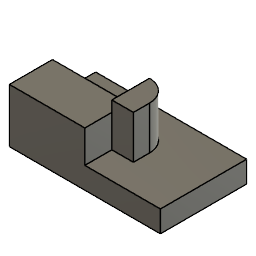
rectangle (Autodesk Fusion 360 design; units mm, degrees)
part number: 2026-08-21-15-46-27-767
Autodesk Fusion 360 part; units mm, degrees
sketch "Sketch1" plane through (0, 0, 0) normal (0, 1, 0) x (1, 0, 0)
  line L0 (100, -50) -> (-40, -50)
  line L1 (-40, -50) -> (-40, 30)
  line L2 (-40, 30) -> (100, 30)
  line L3 (100, 30) -> (100, -50)
  constraint horizontal L0
  constraint vertical L1
  constraint horizontal L2
  constraint vertical L3
extrude "Extrude1" add sketch "Sketch1" along normal blind 20
sketch "Sketch2" plane through (0, 20, 0) normal (0, 1, 0) x (-1, 0, 0)
  line L0 (-100, -30) -> (40, -30)
  line L1 (40, -30) -> (40, 50)
  line L2 (40, 50) -> (-100, 50)
  line L3 (-100, 50) -> (-100, -30)
  line L4 (-30, -30) -> (-30, 50)
  line L5 (-100, 10) -> (40, 10)
  circle A0 centre (-30, 10) radius 20
  constraint midpoint L0 L4.start
  constraint midpoint L2 L4.end
  constraint midpoint L3 L5.start
  constraint midpoint L1 L5.end
  constraint midpoint L5 A0.centre
extrude "Extrude2" add sketch "Sketch2" along normal blind 20 contours L4 L5 A0 picked at (-43.2655, 9.0512)
sketch "Sketch3" plane through (0, 20, 0) normal (0, 1, 0) x (-1, 0, 0)
  line L0 (-50, 10) -> (-30, 10)
  line L1 (-30, 10) -> (-30, -10)
  arc A0 (-50, 10) -> (-30, -10) centre (-30, 10) ccw
  line L2 (-100, -30) -> (40, -30)
  line L3 (40, -30) -> (40, 50)
  line L4 (40, 50) -> (-100, 50)
  line L5 (-100, 50) -> (-100, -30)
  line L6 (-30, 10) -> (40, 10)
  constraint coincident L0.end L1.start
  constraint midpoint L3 L6.end
sketch "Sketch4" plane through (0, 20, 0) normal (0, 1, 0) x (-1, 0, 0)
  line L0 (-30, 50) -> (-30, 10)
  line L1 (-30, 10) -> (40, 10)
  constraint vertical L0
  constraint perpendicular L0 L1
sketch "Sketch5" plane through (0, 20, 0) normal (0, 1, 0) x (-1, 0, 0)
  line L0 (-30, 10) -> (40, -30)
  line L1 (40, -30) -> (40, 10)
  constraint vertical L1
extrude "Extrude3" add 1 faces at (43.2655, 40, 9.0512) along direction (0, 1, 0) blind 20
split_face "SplitFace1" 1 faces at (-16.6667, 20, 10) by curves path "Sketch4" along L0 L1
extrude "Extrude4" add 1 faces at (43.3333, 33.3333, 10) along direction (0, 0, 1) blind 15
extrude "Extrude5" add 1 faces at (-16.6667, 20, 28.3333) along direction (0, 1, 0) blind 30
